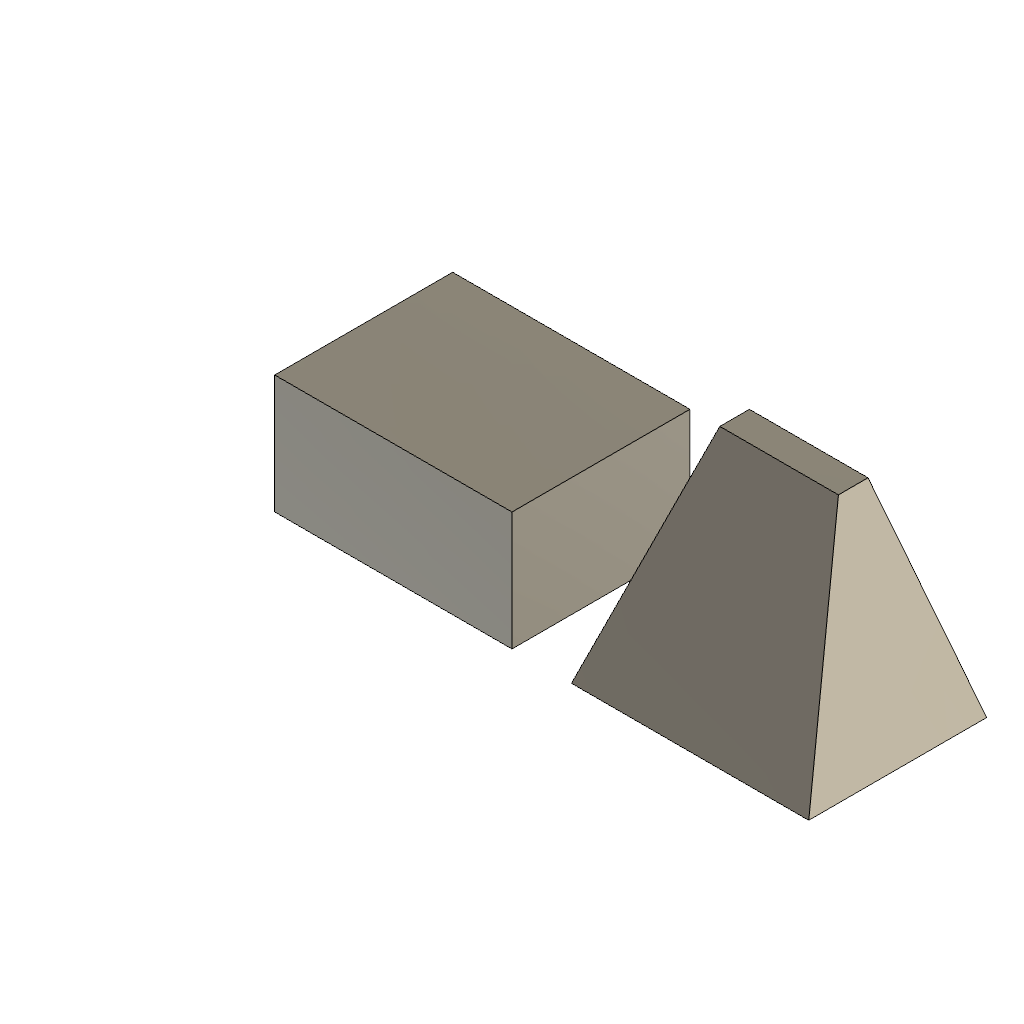
vendor_LoftWedgeBody (Autodesk Fusion 360 design; units mm, degrees)
Autodesk Fusion 360 part; units mm, degrees
sketch "Base sketch" plane through (0, 0, 0) normal (0, 0, 1) x (1, 0, 0)
  line L0 (0, 0) -> (40, 0)
  line L1 (40, 0) -> (40, 30)
  line L2 (40, 30) -> (0, 30)
  line L3 (0, 30) -> (0, 0)
extrude "Base extrude" add sketch "Base sketch" along normal blind 20 makes body 1
sketch "Wedge base" plane through (0, 0, 0) normal (0, 0, 1) x (1, 0, 0)
  line L0 (50, 0) -> (90, 0)
  line L1 (90, 0) -> (90, 30)
  line L2 (90, 30) -> (50, 30)
  line L3 (50, 30) -> (50, 0)
ref_plane "WorkPlane1" through (0, 0, 30) normal (0, 0, 1) x (1, 0, 0)
sketch "Wedge top" plane through (0, 0, 30) normal (0, 0, 1) x (1, 0, 0)
  line L0 (55, 20) -> (75, 20)
  line L1 (75, 20) -> (75, 25)
  line L2 (75, 25) -> (55, 25)
  line L3 (55, 25) -> (55, 20)
loft "Wedge loft" add profiles "Wedge base", "Wedge top" section 1 section 2 separate body makes body 2
equation "height = 20.0 mm"
